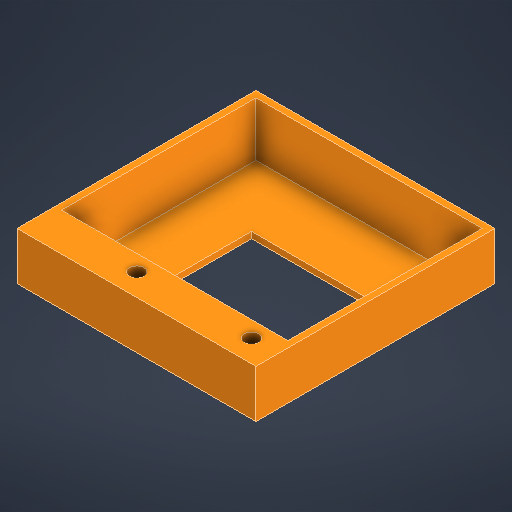
# Autodesk Inventor part: Kugelauffang
Saved by Autodesk Inventor 2027.1 (Build 311270010, 270A)
## iProperties
Created: 2026-11-18
Part Number: Kugelauffang
Material: Generic
Document SubType Name: Modeling
Designer: nicol
Density: 1 g/cm^3
Appearance: Orange
Author: nicol
Autodesk Inventor part; units mm, degrees
ref_plane "YZ Plane" through (0, 0, 0) normal (1, 0, 0) x (0, 1, 0)
ref_plane "XZ Plane" through (0, 0, 0) normal (0, 1, 0) x (-1, 0, 0)
ref_plane "XY Plane" through (0, 0, 0) normal (0, 0, 1) x (1, 0, 0)
sketch "Sketch1" plane through (0, 0, 0) normal (0, 1, 0) x (-1, 0, 0)
  line L0 (0, 0) -> (75, 0)
  line L1 (75, 0) -> (75, -75)
  line L2 (75, -75) -> (0, -75)
  line L3 (0, -75) -> (0, 0)
  dimension "d0" = 75
  dimension "d1" = 75
  constraints: 8 end point, 2 parallel, 1 horizontal, 1 perpendicular
  measures "d0" distance between parallel lines of L2 L0
  measures "d1" distance between parallel lines of L3 L1
extrude "Extrusion1" add sketch "Sketch1" along normal blind 15
sketch "Sketch2" plane through (0, 15, 0) normal (0, 1, 0) x (1, 0, 0)
  circle A0 centre (-8.4, 7) radius 2.25
  circle A1 centre (-44.4, 7) radius 2.25
  line L0 (0, 0) -> (0, 75) projected
  line L1 (-75, 0) -> (0, 0) projected
  dimension "d4" = 4.5
  dimension "d5" = 4.5
  dimension "d6" = 36
  dimension "d7" = 0
  dimension "d8" = 8.4
  dimension "d9" = 7
  constraints: 2 centre point
  measures "d4" diameter of A0
  measures "d5" diameter of A1
  measures "d6" distance of A0.centre A1.centre
  measures "d7" vertical distance of A0.centre A1.centre
  measures "d8" distance from line of L0 A0.centre
  measures "d9" distance from line of L1 A0.centre
extrude "Extrusion2" cut sketch "Sketch2" against normal up to surface (15 mm away)
sketch "Sketch4" plane through (0, 15, 0) normal (0, 1, 0) x (1, 0, 0)
  line L0 (-6, 16) -> (-50.4, 16)
  line L1 (-50.4, 16) -> (-50.4, 49)
  line L2 (-50.4, 49) -> (-6, 49)
  line L3 (-6, 49) -> (-6, 16)
  line L4 (-75, 0) -> (0, 0) projected
  line L5 (0, 0) -> (0, 75) projected
  line L6 (-75, 75) -> (-75, 0) projected
  line L7 (0, 75) -> (-75, 75) projected
  dimension "d12" = 16
  dimension "d13" = 6
  dimension "d14" = 24.6
  dimension "d15" = 26
  constraints: 8 end point, 2 parallel, 1 horizontal, 1 perpendicular
  measures "d12" distance between parallel lines of L4 L0
  measures "d13" distance between parallel lines of L5 L3
  measures "d14" distance between parallel lines of L6 L1
  measures "d15" distance between parallel lines of L7 L2
extrude "Extrusion3" cut sketch "Sketch4" against normal up to surface (15 mm away) contours L0 L1 L2 L3
sketch "Sketch5" plane through (0, 15, 0) normal (0, 1, 0) x (1, 0, 0)
  line L0 (-6, 49) -> (-6, 16) projected
  line L1 (-6, 16) -> (-69, 16)
  line L2 (-69, 16) -> (-69, 69)
  line L3 (-69, 69) -> (-6, 69)
  line L4 (-6, 69) -> (-6, 16)
  line L5 (-75, 75) -> (-75, 0) projected
  line L6 (0, 75) -> (-75, 75) projected
  point P0 (0, 0)
  dimension "d28" = 6
  dimension "d29" = 6
  constraints: 8 end point, 2 parallel, 1 horizontal, 1 perpendicular
  measures "d28" distance between parallel lines of L5 L2
  measures "d29" distance between parallel lines of L6 L3
extrude "Extrusion4" cut sketch "Sketch5" against normal blind 13
chamfer "Chamfer4" distance 4 distance2 13 3 edges at (-6, 15, -42.5) (-37.5, 15, -69) (-69, 15, -42.5) measured on face at (-73, 15, -30.3333)
chamfer "Chamfer6" distance 4 distance2 13 1 edges at (-37.5, 15, -16) measured on face at (-39.8904, 15, -13.7445)
body "Solid1"
